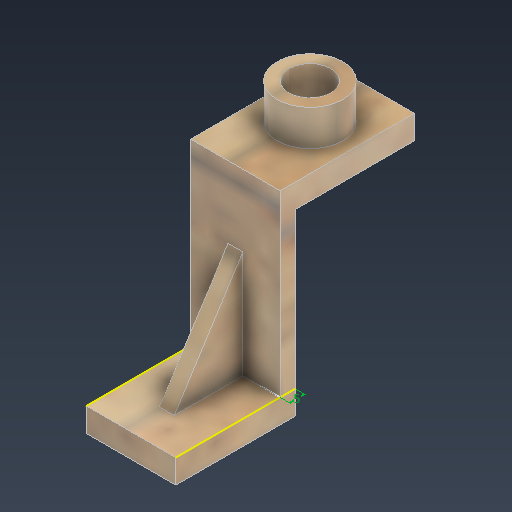
# Autodesk Inventor part: IsometricFive
Saved by Autodesk Inventor 2026.4 (Build 304435000, 435)
## iProperties
Created: 2026-09-06
Part Number: IsometricFive
Material: Generic
Document SubType Name: Modeling
Designer: YmCris
Density: 1 g/cm^3
Appearance: Natural Maple - Glossy Dark Tint
Author: YmCris
Autodesk Inventor part; units mm, degrees
ref_plane "XZ Plane" through (0, 0, 0) normal (0, 1, 0) x (-1, 0, 0)
ref_plane "XY Plane" through (0, 0, 0) normal (0, 0, 1) x (1, 0, 0)
sketch "Sketch1" plane through (0, 0, 0) normal (0, 1, 0) x (-1, 0, 0)
  line L0 (-15, -20) -> (15, -20)
  line L1 (15, -20) -> (15, 20)
  line L2 (15, 20) -> (-15, 20)
  line L3 (-15, 20) -> (-15, -20)
  line L4 (-15, -20) -> (15, 20) construction
  line L5 (15, -20) -> (-15, 20) construction
  point P0 (0, 0)
  dimension "d0" = 30
  dimension "d1" = 40
  constraints: 12 end point, 2 midpoint, 2 parallel, 1 horizontal, 1 perpendicular
  measures "d0" distance of L2.end L1.end
  measures "d1" distance of L1.end L0.end
extrude "Extrusion1" add sketch "Sketch1" along normal blind 8
sketch "Sketch2" plane through (0, 8, 0) normal (0, 1, 0) x (1, 0, 0)
  line L0 (-15, 20) -> (-15, -20) projected
  line L1 (15, -20) -> (15, 20) projected
  line L2 (-15, 20) -> (15, 20)
  line L3 (15, 20) -> (15, 15)
  line L4 (15, 15) -> (-15, 15)
  line L5 (-15, 15) -> (-15, 20)
  point P0 (0, 0)
  dimension "d4" = 5
  constraints: 8 end point, 2 parallel, 1 horizontal, 1 perpendicular, 1 point on line
  measures "d4" distance of L2.end L3.end
extrude "Extrusion2" add sketch "Sketch2" along normal blind 60
ref_plane "Work Plane1" through (0, 0, 0) normal (1, 0, 0) x (0, 1, 0)
sketch "Sketch3" plane through (0, 0, 0) normal (1, 0, 0) x (0, 1, 0)
  line L0 (68, -15) -> (68, -20) projected
  line L1 (8, -15) -> (68, -15) projected
  line L2 (8, 20) -> (8, -15) projected
  line L3 (8, 8) -> (44, -15)
  line L4 (0, 20) -> (8, 20) projected
  dimension "d11" = 24
  dimension "d12" = 12
  constraints: 2 end point, 2 point on line
  measures "d11" distance from line of L3.end L0
  measures "d12" distance from line of L4 L3.start
extrude "Rib1" add sketch "Sketch3" along normal mid plane 5 rib yes fills toward (25.9731, -3.5421) open curves L3
sketch "Sketch4" plane through (15, 0, -20) normal (0, 0, -1) x (-1, 0, 0)
  line L0 (0, 0) -> (0, 68) projected
  line L1 (0, 68) -> (30, 68)
  line L2 (30, 68) -> (30, 60)
  line L3 (30, 60) -> (0, 60)
  line L4 (0, 60) -> (0, 68)
  point P0 (15, 0)
  dimension "d19" = 30
  constraints: 8 end point, 2 parallel, 1 horizontal, 1 perpendicular
  measures "d19" distance of L2.end L3.end
extrude "Extrusion3" add sketch "Sketch4" along normal blind 40
sketch "Sketch9" plane through (0, 68, 0) normal (0, 1, 0) x (1, 0, 0)
  line L0 (15, 20) -> (-15, 20) construction
  line L1 (15, 20) -> (-15, 20) construction
  circle A0 centre (0, 40) radius 11
  point P0 (0, 0)
  dimension "d23" = 22
  constraints: 2 end point, 1 centre point, 1 coincident, 1 horizontal
  measures "d23" diameter of A0
extrude "Extrusion4" add sketch "Sketch9" along normal blind 12
shell "Shell1" thickness 4 removed faces 1 at (6.7466, 80, -37.914)
body "Solid1"
